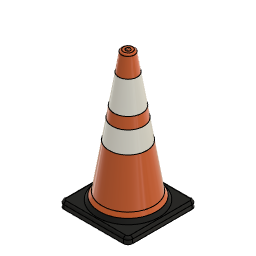
Traffic Cone (Autodesk Fusion 360 design; units mm, degrees)
Autodesk Fusion 360 part; units mm, degrees
note: some values were not read from the file. Set by a fixed rule: which face or edge a step refers to.
sketch "Sketch2" plane through (0, 0, 0) normal (0, 1, 0) x (1, 0, 0)
  line L0 (0, 0) -> (0, -100)
  line L1 (0, -100) -> (3.3286, -100)
  line L2 (4.739, -98.7987) -> (19.0476, -10)
  line L3 (19.0476, -10) -> (22.7273, -4.5455)
  line L4 (22.7273, -4.5455) -> (25.1889, -4.5455)
  line L5 (25.1889, -4.5455) -> (25.1889, 0)
  line L6 (25.1889, 0) -> (0, 0)
  line L7 (20.8874, -7.2727) -> (0, -7.2727)
  line L8 (0, -42.5532) -> (13.8022, -42.5532)
  line L9 (0, -56.8389) -> (11.5002, -56.8389)
  line L10 (0, -64.5161) -> (10.2632, -64.5161)
  line L11 (0, -85.7927) -> (6.8347, -85.7927)
  line L12 (0, -99.2) -> (3.3286, -99.2)
  line L13 (3.9492, -98.6714) -> (18.2858, -9.6987)
  line L14 (18.2858, -9.6987) -> (24.8286, 0)
  line L15 (22.7273, -4.5455) -> (22.7273, 0)
  arc A0 (3.3286, -100) -> (4.739, -98.7987) centre (3.3286, -98.5714) ccw
  line L16 (3.3286, -100) -> (3.3286, 0)
  line L17 (1.6643, -100) -> (1.6643, 0)
  arc A1 (3.3286, -99.2) -> (3.9492, -98.6714) centre (3.3286, -98.5714) ccw construction
  line L18 (3.3286, -99.2) -> (3.9492, -98.6714)
  point P0 (4.5455, -100)
  dimension "d4" = 100
  dimension "d5" = 4.5455
  dimension "d6" = 19.0476
  dimension "d7" = 25.1889
  dimension "d8" = 4.5455
  dimension "d9" = 22.7273
  dimension "d10" = 10
  dimension "d18" = 42.5532
  dimension "d20" = 64.5161
  dimension "d21" = 14.2857
  dimension "d22" = 21.2766
  dimension "d29" = 0.8
  dimension "d30" = 0.8
  dimension "d31" = 0.8
  dimension "d43" = 1.4286
  dimension "d45" = 0.6286
  constraint coincident L0.start L6.end
  constraint vertical L0
  constraint perpendicular L0 L1
  constraint parallel L1 L4
  constraint perpendicular L4 L5
  constraint perpendicular L5 L6
  constraint midpoint L3 L7.start
  constraint coincident L0 L7.end
  constraint perpendicular L0 L7
  constraint coincident L0 L8.start
  constraint coincident L2 L8.end
  constraint perpendicular L0 L8
  constraint coincident L0 L9.start
  constraint perpendicular L0 L9
  constraint coincident L0 L10.start
  constraint coincident L2 L10.end
  constraint perpendicular L0 L10
  constraint coincident L2 L9.end
  constraint coincident L0 L11.start
  constraint coincident L2 L11.end
  constraint perpendicular L0 L11
  constraint coincident L0 L12.start
  constraint perpendicular L0 L12
  constraint coincident L6 L15.end
  constraint perpendicular L6 L15
  constraint parallel L2 L13
  constraint parallel L3 L14
  constraint coincident P0 L1
  constraint coincident P0 L2
  constraint tangent L1 A0
  constraint tangent L2 A0
  constraint coincident L6 L16.end
  constraint vertical L16
  constraint coincident L6 L17.end
  constraint perpendicular L6 L17
  constraint midpoint L1 L17.start
  constraint tangent L13 A1
  constraint tangent L12 A1
  constraint coincident L6 L14.end
  measures "d4" distance of L0.start L0.end
  measures "d5" distance of L0.end P0
  measures "d6" distance of L0 L2.end
  measures "d7" distance of L5.end L0.start
  measures "d8" distance of L4.end L5.end
  measures "d9" distance of L0 L3.end
  measures "d10" distance of L2.end L6
  measures "d18" distance of L0.start L8
  measures "d20" distance of L0.start L10
  measures "d21" distance of L8 L9
  measures "d22" distance of L10 L11
  measures "d29" distance of L2 L13
  measures "d30" distance of L3 L14
  measures "d31" distance of L1 L12
  measures "d43" radius of A0
  measures "d45" radius of A1
sketch "Sketch3" plane through (0, 0, 0) normal (0, 0, 1) x (1, 0, 0)
  line L0 (25.1889, -25.1889) -> (-25.1889, -25.1889)
  line L1 (-25.1889, -25.1889) -> (-25.1889, 25.1889)
  line L2 (-25.1889, 25.1889) -> (25.1889, 25.1889)
  line L3 (25.1889, 25.1889) -> (25.1889, -25.1889)
  line L4 (25.1889, -25.1889) -> (-25.1889, 25.1889) construction
  line L5 (-25.1889, -25.1889) -> (25.1889, 25.1889) construction
  circle A0 centre (0, 0) radius 22.7273
  point P0 (25.1889, 0)
  point P1 (22.7273, 0)
  constraint horizontal L0
  constraint perpendicular L0 L1
  constraint parallel L0 L2
  constraint parallel L1 L3
  constraint coincident L4 A0.centre
  constraint coincident L5 A0.centre
  constraint coincident A0.centre origin
  constraint coincident L3 P0
  constraint equal L0 L1
  constraint coincident P1 A0
revolve "Revolve1" add sketch "Sketch2" angle 360 about axis through (0, 0, 0) along (0, 0, 1) contours L3 L7 L14 L15 | L2 L3 L7 L8 L13 L14 | L2 L8 L9 L13 | L0 L1 L12 L17 | L2 L9 L10 L13 | L1 L12 L16 L17 | L2 L10 L11 L13 | L2 L11 L13 A0 L16 L18 makes body 1 in component "Traffic Cone"
extrude "Extrude1" add sketch "Sketch3" along normal up to surface (4.5455 mm away) bodies 1 in component "Traffic Cone"
fillet "Fillet1" radius 3.3333 4 edges at (25.1889, -25.1889, 2.2727) (-25.1889, -25.1889, 2.2727) (25.1889, 25.1889, 2.2727) (-25.1889, 25.1889, 2.2727) on bodies 1 in component "Traffic Cone"
fillet "Fillet2" radius 1.6667 8 edges at (0, -25.1889, 4.5455) (-24.2126, -24.2126, 4.5455) (-25.1889, 0, 4.5455) (-24.2126, 24.2126, 4.5455) (0, 25.1889, 4.5455) (24.2126, 24.2126, 4.5455) (25.1889, 0, 4.5455) (24.2126, -24.2126, 4.5455) on bodies 1 in component "Traffic Cone"
split_face "SplitFace1" 1 faces at (21.474, -1.0717, 6.3636) by curves path "Sketch2" along L7 on bodies 1 in component "Traffic Cone"
split_face "SplitFace2" 1 faces at (-6.461, -16.4624, 18.457) by curves path "Sketch2" along L8 on bodies 1 in component "Traffic Cone"
split_face "SplitFace3" 1 faces at (12.7945, 1.9285, 47.9099) by curves path "Sketch2" along L9 on bodies 1 in component "Traffic Cone"
split_face "SplitFace4" 1 faces at (10.6289, 1.6021, 61.5011) by curves path "Sketch2" along L10 on bodies 1 in component "Traffic Cone"
split_face "SplitFace5" 1 faces at (9.5416, 1.4382, 68.3253) by curves path "Sketch2" along L11 on bodies 1 in component "Traffic Cone"
revolve "Revolve1'" add sketch "Sketch2" angle 360 about axis through (0, 0, 0) along (0, 0, 1) separate body contours L0 L6 L7 L17 | L0 L7 L8 L17 | L0 L8 L9 L17 | L0 L9 L10 L17 | L0 L10 L11 L17 | L0 L11 L12 L17 | L0 L1 L12 L17 makes body 2 in component "Traffic Cone Colour Change"
component "Traffic Cone" placed x (1, 0, 0) y (0, 1, 0) z (0, 0, 1) at (0, 0, 0)
component "Traffic Cone Colour Change" placed x (1, 0, 0) y (0, 1, 0) z (0, 0, 1) at (0, 0, 0)
equation "d4 = height"
equation "d5 = d4 / 22"
equation "d6 = d4 / 5.25"
equation "d7 = d4 / 3.97"
equation "d8 = d4 / 22"
equation "d9 = d4 / 4.4"
equation "d10 = d4 / 10"
equation "d18 = d4 / 2.35"
equation "d20 = d4 / 1.55"
equation "d21 = d4 / 7"
equation "d22 = d4 / 4.7"
equation "height = 100 mm"
equation "d30 = d29"
equation "d31 = d29"
equation "d37 = height / 30"
equation "d39 = height / 60"
equation "d43 = height / 70"
equation "d45 = d43 - d29"
